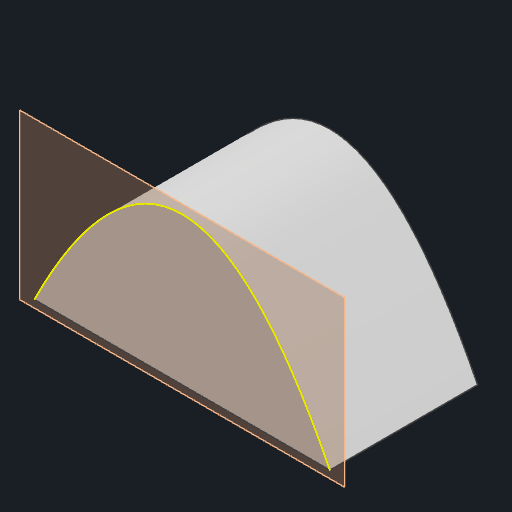
# Autodesk Inventor part: projected
Saved by Autodesk Inventor 2026.1 (Build 301233000, 233)
## iProperties
Created: 2026-10-30
Part Number: projected
Material: Generic
Document SubType Name: Modeling
Designer: anony
Density: 1 g/cm^3
Appearance: Default
Author: anony
Autodesk Inventor part; units mm, degrees
ref_plane "YZ Plane" through (0, 0, 0) normal (1, 0, 0) x (0, 1, 0)
ref_plane "XZ Plane" through (0, 0, 0) normal (0, 1, 0) x (-1, 0, 0)
sketch "Sketch1" plane through (0, 0, 0) normal (0, 0, 1) x (1, 0, 0)
  spline S0 degree 4 poles (0, 0) (0.625, 1.2499) (1.875, 3.5414) (3.75, 6.3539) (6.25, 8.854) (8.75, 10.1042) (11.25, 10.1042) (13.75, 8.854) (16.25, 6.3539) (18.125, 3.5414) (19.375, 1.2499) (20, 0) knots 0 0 0 0 0 0.125 0.25 0.375 0.5 0.625 0.75 0.875 1 1 1 1 1
  line L0 (20, 0) -> (0, 0)
  point P0 (10, 10)
  constraints: 2 end point, 3 other
extrude "Extrusion1" add sketch "Sketch1" along normal blind 10
ref_plane "Work Plane1" through (0, 0, 10) normal (0, 0, 1) x (1, 0, 0)
sketch "Sketch2" plane through (0, 0, 10) normal (0, 0, 1) x (1, 0, 0)
  constraints: 1 horizontal alignment
body "Solid1"
